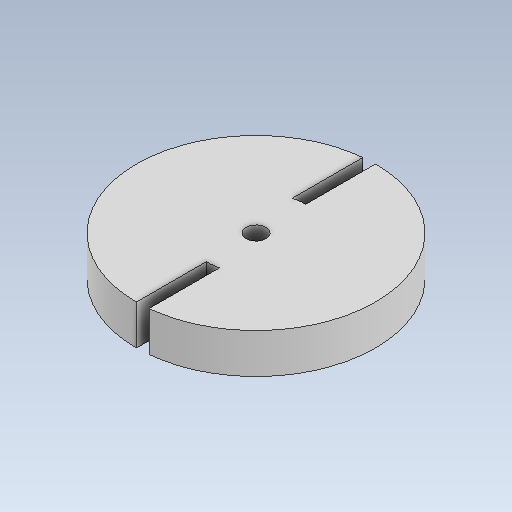
# Autodesk Inventor part: Waffendummy für optimierung
Saved by Autodesk Inventor 2026.4 (Build 304435030, 435C)
## iProperties
Created: 2026-11-20
Part Number: Waffendummy für optimierung
Material: Generisch
Document SubType Name: Modeling
Designer: weira
Density: 1 g/cm^3
Appearance: Vorgabe
Author: weira
Autodesk Inventor part; units mm, degrees
ref_plane "YZ Plane" through (0, 0, 0) normal (1, 0, 0) x (0, 1, 0)
ref_plane "XZ Plane" through (0, 0, 0) normal (0, 1, 0) x (-1, 0, 0)
ref_plane "XY Plane" through (0, 0, 0) normal (0, 0, 1) x (1, 0, 0)
sketch "Skizze1" plane through (0, 0, 0) normal (0, 0, 1) x (1, 0, 0)
  circle A0 centre (-3.665, 0) radius 12.5
  circle A1 centre (-3.665, 0) radius 30
  line L0 (-3.665, 30) -> (26.335, 30)
  line L1 (26.335, 30) -> (26.335, 0)
  line L2 (26.335, 0) -> (-3.665, 0)
  line L3 (-3.665, 0) -> (-3.665, 30)
  line L4 (-33.665, 0) -> (-33.665, -30)
  line L5 (-33.665, -30) -> (-3.665, -30)
  line L6 (-3.665, -30) -> (-3.665, 0)
  line L7 (-3.665, 0) -> (-0.665, 0)
  line L8 (-0.665, 0) -> (-0.665, -30)
  line L9 (-0.665, -30) -> (-3.665, -30)
  line L10 (-3.665, -30) -> (-3.665, 0)
  line L11 (-3.665, 0) -> (-6.665, 0)
  line L12 (-6.665, 0) -> (-6.665, 30)
  line L13 (-6.665, 30) -> (-3.665, 30)
  line L14 (-3.665, 30) -> (-3.665, 0)
  point P0 (-3.665, 12.5)
  point P1 (-3.665, -30)
  point P2 (-3.665, -12.5)
  point P3 (8.835, 0)
  point P4 (-6.665, 29.8496)
  point P5 (-0.665, -29.8496)
  point P6 (-6.665, 12.1347)
  point P7 (-0.665, -12.1347)
  dimension "d0" = 25
  dimension "d1" = 60
  dimension "d11" = 3
  dimension "d13" = 3
  constraints: 30 end point, 7 parallel, 3 horizontal, 3 perpendicular, 3 point on circle, 2 centre point, 2 coincident
  measures "d0" diameter of A0
  measures "d1" diameter of A1
  measures "d11" distance between parallel lines of L6 L8
  measures "d13" distance between parallel lines of L3 L12
extrude "Extrusion1" add sketch "Skizze1" along normal blind 10 contours L2 L3 A0 | L2 A1 L8 A0 | A0 L3 A1 L2 | A0 L8 L2 | L3 L11 L12 A0 | A0 L6 L2 L8 | L12 L11 L6 A0 | A0 L6 A1 L12
sketch "Skizze2" plane through (0, 0, 10) normal (0, 0, 1) x (1, 0, 0)
  arc A0 (-6.665, 29.8496) -> (-3.665, -30) centre (-3.665, 0) ccw projected
  line L0 (-6.665, 12.1347) -> (-6.665, 29.8496) projected
  arc A1 (-3.665, 12.5) -> (-6.665, 12.1347) centre (-3.665, 0) ccw projected
  line L1 (-3.665, 30) -> (-3.665, 12.5) projected
  arc A2 (-0.665, -29.8496) -> (-3.665, 30) centre (-3.665, 0) ccw projected
  line L2 (-0.665, -12.1347) -> (-0.665, -29.8496) projected
  arc A3 (-3.665, -12.5) -> (-0.665, -12.1347) centre (-3.665, 0) ccw projected
  line L3 (-3.665, -30) -> (-3.665, -12.5) projected
hole "Bohrung1" at (-3.665, 0, 10) direction (0, 0, -1) diameter 5 end through all
